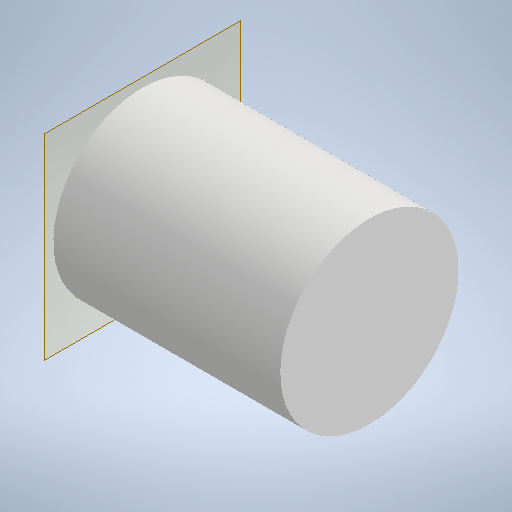
# Autodesk Inventor part: RDS-SPF-2-120-2001 bush
Saved by Autodesk Inventor 2026 (Build 300175000, 175)
## iProperties
Created: 2026-10-27
Part Number: RDS-SPF-2-120-2001 bush
Material: Типовые
Document SubType Name: Modeling
Designer: user
Density: 1 g/cm^3
Appearance: По умолчанию
Author: user
Autodesk Inventor part; units mm, degrees
ref_plane "YZ Plane" through (0, 0, 0) normal (1, 0, 0) x (0, 1, 0)
ref_plane "XZ Plane" through (0, 0, 0) normal (0, 1, 0) x (-1, 0, 0)
ref_plane "XY Plane" through (0, 0, 0) normal (0, 0, 1) x (1, 0, 0)
ref_plane "РабПлоскость1" through (-757.5345, 125.3906, -607.8104) normal (1, 0, 0) x (0, -1, 0)
sketch "Эскиз1" plane through (-757.5345, 125.3906, -607.8104) normal (1, 0, 0) x (0, -1, 0)
  circle A0 centre (0, 0) radius 27.5
  point P0 (125.3906, -607.8104)
  dimension "d0" = 55
  constraints: 1 centre point
  measures "d0" diameter of A0
extrude "Выдавливание1" add sketch "Эскиз1" along normal blind 70
